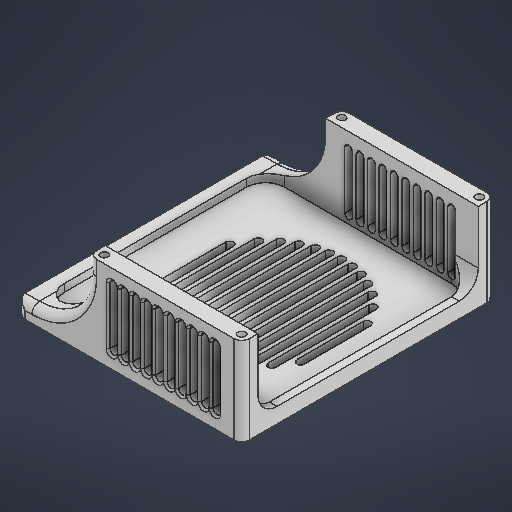
# Autodesk Inventor part: FLOOR PARTS
Saved by Autodesk Inventor 2027.1 (Build 311270010, 270A)
## iProperties
Created: 2026-10-10
Part Number: FLOOR PARTS
Material: 일반
Document SubType Name: Modeling
Designer: work
Density: 1 g/cm^3
Appearance: 기본값
Author: work
Autodesk Inventor part; units mm, degrees
ref_plane "YZ Plane" through (0, 0, 0) normal (1, 0, 0) x (0, 1, 0)
ref_plane "XZ Plane" through (0, 0, 0) normal (0, 1, 0) x (-1, 0, 0)
ref_plane "XY Plane" through (0, 0, 0) normal (0, 0, 1) x (1, 0, 0)
sketch "스케치1" plane through (0, 0, 0) normal (0, 1, 0) x (-1, 0, 0)
  line L0 (0, 0) -> (72, 0) construction
  line L1 (72, 0) -> (72, -124.5) construction
  line L2 (72, -124.5) -> (0, -124.5) construction
  line L3 (0, -124.5) -> (0, 0) construction
  line L4 (76, -128.5) -> (76, 4)
  line L5 (76, 4) -> (-4, 4)
  line L6 (-4, 4) -> (-4, -128.5)
  line L7 (-4, -128.5) -> (76, -128.5)
  circle A0 centre (72, 0) radius 2
  circle A1 centre (0, 0) radius 2
  circle A2 centre (0, -124.5) radius 2
  circle A3 centre (72, -124.5) radius 2
  line L8 (97.5, -4.5) -> (10, -4.5)
  line L9 (0, -14.5) -> (0, -110)
  line L10 (10, -120) -> (97.5, -120)
  line L11 (107.5, -110) -> (107.5, -14.5)
  arc A4 (10, -4.5) -> (0, -14.5) centre (10, -14.5) ccw
  arc A5 (0, -110) -> (10, -120) centre (10, -110) ccw
  line L12 (-4, -4.5) -> (10, -4.5)
  line L13 (-4, -120) -> (10, -120)
  arc A6 (107.5, -14.5) -> (97.5, -4.5) centre (97.5, -14.5) ccw
  arc A7 (97.5, -120) -> (107.5, -110) centre (97.5, -110) ccw
  line L14 (76, 4) -> (113.5, 4)
  line L15 (113.5, 4) -> (113.5, -128.5)
  line L16 (113.5, -128.5) -> (76, -128.5)
  line L17 (76, -128.5) -> (76, 4)
  point P0 (0, -120)
  point P1 (0, -4.5)
  point P2 (107.5, -120)
  point P3 (0, -62.25)
  point P4 (76, -4.5)
  point P5 (76, -120)
  dimension "d0" = 124.5
  dimension "d1" = 72
  dimension "d2" = 4
  dimension "d3" = 4
  dimension "d4" = 4
  dimension "d5" = 4
  dimension "d6" = 4
  dimension "d7" = 115.5
  dimension "d8" = 107.5
  dimension "d9" = 10
  dimension "d16" = 10
  dimension "d17" = 6
  constraints: 36 end point, 9 parallel, 8 centre point, 8 point on circle, 8 point on line, 8 tangent, 4 coincident, 4 horizontal, 4 perpendicular, 2 equal radius, 2 midpoint, 3 other
  measures "d0" distance of L2.end L0.start
  measures "d1" distance of L0.start L0.end
  measures "d2" distance between parallel lines of L1 L4
  measures "d3" diameter of A0
  measures "d4" diameter of A1
  measures "d5" diameter of A2
  measures "d6" diameter of A3
  measures "d7" distance of point (0, -4.5) point (0, -120)
  measures "d8" distance of point (0, -120) point (107.5, -120)
  measures "d9" radius of A4
  measures "d16" radius of A6
  measures "d17" distance between parallel lines of L15 L11
extrude "돌출1" add sketch "스케치1" along normal blind 4 contours L7 L6 L13 L10 L4 | L10 A5 L9 A4 L8 L4 | L4 L8 A6 L11 A7 L10 | L8 L12 L6 L5 L4 | L13 L6 L12 A4 L9 A5 | A0 | A1 | A2 | A3
extrude "돌출2" add sketch "스케치1" along normal blind 8 contours L7 L6 L13 L10 L4 | L4 L10 A7 L11 A6 L8 L14 L15 L16 | L8 L12 L6 L5 L4 | L13 L6 L12 A4 L9 A5
extrude "돌출3" add sketch "스케치1" along normal blind 46 contours L7 L6 L13 L10 L4 | L8 L12 L6 L5 L4
fillet "모깎기1" radius 30 2 edges at (-76, 8, -124.25) (-76, 8, -0.25)
sketch "스케치2" plane through (4, 0, -128.5) normal (0, 0, -1) x (-1, 0, 0)
  line L0 (8, 38) -> (8, 8) construction
  line L1 (6, 38) -> (6, 8)
  line L2 (10, 8) -> (10, 38)
  arc A0 (10, 38) -> (6, 38) centre (8, 38) ccw
  arc A1 (6, 8) -> (10, 8) centre (8, 8) ccw
  line L3 (0, 0) -> (117.5, 0) projected
  line L4 (0, 46) -> (80, 46) projected
  line L5 (0, 0) -> (0, 46) projected
  line L6 (14, 38) -> (14, 8) construction
  line L7 (12, 38) -> (12, 8)
  line L8 (16, 8) -> (16, 38)
  arc A2 (16, 38) -> (12, 38) centre (14, 38) ccw
  arc A3 (12, 8) -> (16, 8) centre (14, 8) ccw
  line L9 (20, 38) -> (20, 8) construction
  line L10 (18, 38) -> (18, 8)
  line L11 (22, 8) -> (22, 38)
  arc A4 (22, 38) -> (18, 38) centre (20, 38) ccw
  arc A5 (18, 8) -> (22, 8) centre (20, 8) ccw
  line L12 (26, 38) -> (26, 8) construction
  line L13 (24, 38) -> (24, 8)
  line L14 (28, 8) -> (28, 38)
  arc A6 (28, 38) -> (24, 38) centre (26, 38) ccw
  arc A7 (24, 8) -> (28, 8) centre (26, 8) ccw
  line L15 (32, 38) -> (32, 8) construction
  line L16 (30, 38) -> (30, 8)
  line L17 (34, 8) -> (34, 38)
  arc A8 (34, 38) -> (30, 38) centre (32, 38) ccw
  arc A9 (30, 8) -> (34, 8) centre (32, 8) ccw
  line L18 (38, 38) -> (38, 8) construction
  line L19 (36, 38) -> (36, 8)
  line L20 (40, 8) -> (40, 38)
  arc A10 (40, 38) -> (36, 38) centre (38, 38) ccw
  arc A11 (36, 8) -> (40, 8) centre (38, 8) ccw
  line L21 (44, 38) -> (44, 8) construction
  line L22 (42, 38) -> (42, 8)
  line L23 (46, 8) -> (46, 38)
  arc A12 (46, 38) -> (42, 38) centre (44, 38) ccw
  arc A13 (42, 8) -> (46, 8) centre (44, 8) ccw
  line L24 (50, 38) -> (50, 8) construction
  line L25 (48, 38) -> (48, 8)
  line L26 (52, 8) -> (52, 38)
  arc A14 (52, 38) -> (48, 38) centre (50, 38) ccw
  arc A15 (48, 8) -> (52, 8) centre (50, 8) ccw
  line L27 (56, 38) -> (56, 8) construction
  line L28 (54, 38) -> (54, 8)
  line L29 (58, 8) -> (58, 38)
  arc A16 (58, 38) -> (54, 38) centre (56, 38) ccw
  arc A17 (54, 8) -> (58, 8) centre (56, 8) ccw
  line L30 (62, 38) -> (62, 8) construction
  line L31 (60, 38) -> (60, 8)
  line L32 (64, 8) -> (64, 38)
  arc A18 (64, 38) -> (60, 38) centre (62, 38) ccw
  arc A19 (60, 8) -> (64, 8) centre (62, 8) ccw
  line L33 (68, 38) -> (68, 8) construction
  line L34 (66, 38) -> (66, 8)
  line L35 (70, 8) -> (70, 38)
  arc A20 (70, 38) -> (66, 38) centre (68, 38) ccw
  arc A21 (66, 8) -> (70, 8) centre (68, 8) ccw
  line L36 (74, 38) -> (74, 8) construction
  line L37 (72, 38) -> (72, 8)
  line L38 (76, 8) -> (76, 38)
  arc A22 (76, 38) -> (72, 38) centre (74, 38) ccw
  arc A23 (72, 8) -> (76, 8) centre (74, 8) ccw
  point P0 (4, 0)
  point P1 (8, 23)
  point P2 (14, 23)
  point P3 (20, 23)
  point P4 (26, 23)
  point P5 (32, 23)
  point P6 (38, 23)
  point P7 (44, 23)
  point P8 (50, 23)
  point P9 (56, 23)
  point P10 (62, 23)
  point P11 (68, 23)
  point P12 (74, 23)
  dimension "d19" = 8
  dimension "d20" = 4
  dimension "d21" = 8
  dimension "d22" = 8
  dimension "d25" = 6
  constraints: 96 end point, 48 point on circle, 24 centre point, 4 tangent, 1 horizontal, 1 midpoint, 1 parallel, 1 vertical, 132 other
  measures "d19" distance from line of L3 L0.end
  measures "d20" distance between parallel lines of L2 L1
  measures "d21" distance from line of L4 L0.start
  measures "d22" distance between parallel lines of L5 L0
  measures "d25" distance of L1.start L7.start
extrude "돌출4" cut sketch "스케치2" against normal through all contours A2 L8 A3 L7 | A4 L11 A5 L10 | A6 L14 A7 L13 | A8 L17 A9 L16 | A10 L20 A11 L19 | A12 L23 A13 L22 | A14 L26 A15 L25 | A16 L29 A17 L28 | A18 L32 A19 L31 | A20 L35 A21 L34
fillet "모깎기2" radius 10 2 edges at (-2, 8, -4.5) (-2, 8, -120)
fillet "모깎기3" radius 4 10 edges at (4, 23, -128.5) (4, 23, 4) (-113.5, 4, -128.5) (-113.5, 4, 4) (-84.7868, 16.7868, 4) (-109.75, 8, 4) (-76, 42, 4) (-109.75, 8, -128.5) (-76, 42, -128.5) (-84.7868, 16.7868, -128.5)
sketch "스케치3" plane through (0, 4, 0) normal (0, 1, 0) x (1, 0, 0)
  circle A0 centre (-50, 62.25) radius 40 construction
  line L0 (0, 110) -> (0, 14.5) projected
  line L1 (-90, 62.25) -> (-10, 62.25) construction
  line L2 (-50, 102.25) -> (-50, 22.25) construction
  line L3 (-52, 102.25) -> (-52, 22.25)
  line L4 (-48, 22.25) -> (-48, 102.25)
  arc A1 (-48, 102.25) -> (-52, 102.25) centre (-50, 102.25) ccw
  arc A2 (-52, 22.25) -> (-48, 22.25) centre (-50, 22.25) ccw
  line L5 (-56, 101.7974) -> (-56, 22.7026) construction
  line L6 (-58, 101.7974) -> (-58, 22.7026)
  line L7 (-54, 22.7026) -> (-54, 101.7974)
  arc A3 (-54, 101.7974) -> (-58, 101.7974) centre (-56, 101.7974) ccw
  arc A4 (-58, 22.7026) -> (-54, 22.7026) centre (-56, 22.7026) ccw
  line L8 (-62, 100.4076) -> (-62, 24.0924) construction
  line L9 (-64, 100.4076) -> (-64, 24.0924)
  line L10 (-60, 24.0924) -> (-60, 100.4076)
  arc A5 (-60, 100.4076) -> (-64, 100.4076) centre (-62, 100.4076) ccw
  arc A6 (-64, 24.0924) -> (-60, 24.0924) centre (-62, 24.0924) ccw
  line L11 (-68, 97.9711) -> (-68, 26.5289) construction
  line L12 (-70, 97.9711) -> (-70, 26.5289)
  line L13 (-66, 26.5289) -> (-66, 97.9711)
  arc A7 (-66, 97.9711) -> (-70, 97.9711) centre (-68, 97.9711) ccw
  arc A8 (-70, 26.5289) -> (-66, 26.5289) centre (-68, 26.5289) ccw
  line L14 (-74, 94.25) -> (-74, 30.25) construction
  line L15 (-76, 94.25) -> (-76, 30.25)
  line L16 (-72, 30.25) -> (-72, 94.25)
  arc A9 (-72, 94.25) -> (-76, 94.25) centre (-74, 94.25) ccw
  arc A10 (-76, 30.25) -> (-72, 30.25) centre (-74, 30.25) ccw
  line L17 (-80, 88.7075) -> (-80, 35.7925) construction
  line L18 (-82, 88.7075) -> (-82, 35.7925)
  line L19 (-78, 35.7925) -> (-78, 88.7075)
  arc A11 (-78, 88.7075) -> (-82, 88.7075) centre (-80, 88.7075) ccw
  arc A12 (-82, 35.7925) -> (-78, 35.7925) centre (-80, 35.7925) ccw
  line L20 (-86, 79.6856) -> (-86, 44.8144) construction
  line L21 (-88, 79.6856) -> (-88, 44.8144)
  line L22 (-84, 44.8144) -> (-84, 79.6856)
  arc A13 (-84, 79.6856) -> (-88, 79.6856) centre (-86, 79.6856) ccw
  arc A14 (-88, 44.8144) -> (-84, 44.8144) centre (-86, 44.8144) ccw
  circle A15 centre (-50, 62.25) radius 40 construction
  line L23 (-10, 62.25) -> (-90, 62.25) construction
  line L24 (-44, 101.7974) -> (-44, 22.7026) construction
  line L25 (-42, 101.7974) -> (-42, 22.7026)
  line L26 (-46, 22.7026) -> (-46, 101.7974)
  arc A16 (-42, 101.7974) -> (-46, 101.7974) centre (-44, 101.7974) ccw
  arc A17 (-46, 22.7026) -> (-42, 22.7026) centre (-44, 22.7026) ccw
  line L27 (-38, 100.4076) -> (-38, 24.0924) construction
  line L28 (-36, 100.4076) -> (-36, 24.0924)
  line L29 (-40, 24.0924) -> (-40, 100.4076)
  arc A18 (-36, 100.4076) -> (-40, 100.4076) centre (-38, 100.4076) ccw
  arc A19 (-40, 24.0924) -> (-36, 24.0924) centre (-38, 24.0924) ccw
  line L30 (-32, 97.9711) -> (-32, 26.5289) construction
  line L31 (-30, 97.9711) -> (-30, 26.5289)
  line L32 (-34, 26.5289) -> (-34, 97.9711)
  arc A20 (-30, 97.9711) -> (-34, 97.9711) centre (-32, 97.9711) ccw
  arc A21 (-34, 26.5289) -> (-30, 26.5289) centre (-32, 26.5289) ccw
  line L33 (-26, 94.25) -> (-26, 30.25) construction
  line L34 (-24, 94.25) -> (-24, 30.25)
  line L35 (-28, 30.25) -> (-28, 94.25)
  arc A22 (-24, 94.25) -> (-28, 94.25) centre (-26, 94.25) ccw
  arc A23 (-28, 30.25) -> (-24, 30.25) centre (-26, 30.25) ccw
  line L36 (-20, 88.7075) -> (-20, 35.7925) construction
  line L37 (-18, 88.7075) -> (-18, 35.7925)
  line L38 (-22, 35.7925) -> (-22, 88.7075)
  arc A24 (-18, 88.7075) -> (-22, 88.7075) centre (-20, 88.7075) ccw
  arc A25 (-22, 35.7925) -> (-18, 35.7925) centre (-20, 35.7925) ccw
  line L39 (-14, 79.6856) -> (-14, 44.8144) construction
  line L40 (-12, 79.6856) -> (-12, 44.8144)
  line L41 (-16, 44.8144) -> (-16, 79.6856)
  arc A26 (-12, 79.6856) -> (-16, 79.6856) centre (-14, 79.6856) ccw
  arc A27 (-16, 44.8144) -> (-12, 44.8144) centre (-14, 44.8144) ccw
  point P0 (0, 0)
  point P1 (0, 62.25)
  point P2 (0, 62.25)
  point P3 (-56, 62.25)
  point P4 (-62, 62.25)
  point P5 (-68, 62.25)
  point P6 (-74, 62.25)
  point P7 (-80, 62.25)
  point P8 (-86, 62.25)
  point P9 (-44, 62.25)
  point P10 (-38, 62.25)
  point P11 (-32, 62.25)
  point P12 (-26, 62.25)
  point P13 (-20, 62.25)
  point P14 (-14, 62.25)
  dimension "d34" = 80
  dimension "d35" = 50
  dimension "d36" = 80
  dimension "d37" = 4
  dimension "d38" = 4
  dimension "d39" = 4
  dimension "d40" = 4
  dimension "d41" = 4
  dimension "d42" = 6
  dimension "d43" = 6
  dimension "d44" = 6
  dimension "d45" = 6
  dimension "d46" = 4
  dimension "d47" = 4
  dimension "d48" = 6
  dimension "d49" = 6
  constraints: 108 end point, 52 point on circle, 44 symmetric about line, 28 tangent, 26 centre point, 13 parallel, 12 point on line, 9 midpoint, 2 vertical, 1 horizontal, 1 horizontal alignment, 33 other
  measures "d35" distance of point (0, 62.25) point (-50, 62.25)
  measures "d36" distance of L1.start L1.end
  measures "d37" diameter of A2
  measures "d38" diameter of A4
  measures "d39" diameter of A6
  measures "d40" diameter of A8
  measures "d41" diameter of A10
  measures "d42" distance between parallel lines of L2 L5
  measures "d43" distance between parallel lines of L8 L5
  measures "d44" distance between parallel lines of L8 L11
  measures "d45" distance between parallel lines of L14 L11
  measures "d46" diameter of A12
  measures "d47" diameter of A14
  measures "d48" distance between parallel lines of L17 L14
  measures "d49" distance between parallel lines of L20 L17
extrude "돌출5" cut sketch "스케치3" against normal through all
sketch "스케치4" plane through (0, 0, 0) normal (0, -1, 0) x (1, 0, 0)
  arc A0 (-46, -101.7974) -> (-42, -101.7974) centre (-44, -101.7974) ccw construction
  line L0 (-46, -101.7974) -> (-46, -22.7026) construction
  arc A1 (-42, -22.7026) -> (-46, -22.7026) centre (-44, -22.7026) ccw construction
  line L1 (-42, -22.7026) -> (-42, -101.7974) construction
  line L2 (-72, -30.25) -> (-72, -94.25) construction
  arc A2 (-76, -94.25) -> (-72, -94.25) centre (-74, -94.25) ccw construction
  line L3 (-76, -94.25) -> (-76, -30.25) construction
  arc A3 (-72, -30.25) -> (-76, -30.25) centre (-74, -30.25) ccw construction
  line L4 (-60, -24.0924) -> (-60, -100.4076) construction
  arc A4 (-64, -100.4076) -> (-60, -100.4076) centre (-62, -100.4076) ccw construction
  line L5 (-64, -100.4076) -> (-64, -24.0924) construction
  arc A5 (-60, -24.0924) -> (-64, -24.0924) centre (-62, -24.0924) ccw construction
  arc A6 (-40, -100.4076) -> (-36, -100.4076) centre (-38, -100.4076) ccw construction
  line L6 (-40, -100.4076) -> (-40, -24.0924) construction
  arc A7 (-36, -24.0924) -> (-40, -24.0924) centre (-38, -24.0924) ccw construction
  line L7 (-36, -24.0924) -> (-36, -100.4076) construction
  arc A8 (-28, -94.25) -> (-24, -94.25) centre (-26, -94.25) ccw construction
  line L8 (-28, -94.25) -> (-28, -30.25) construction
  arc A9 (-24, -30.25) -> (-28, -30.25) centre (-26, -30.25) ccw construction
  line L9 (-24, -30.25) -> (-24, -94.25) construction
  arc A10 (-22, -88.7075) -> (-18, -88.7075) centre (-20, -88.7075) ccw construction
  line L10 (-22, -88.7075) -> (-22, -35.7925) construction
  arc A11 (-18, -35.7925) -> (-22, -35.7925) centre (-20, -35.7925) ccw construction
  line L11 (-18, -35.7925) -> (-18, -88.7075) construction
  arc A12 (-16, -79.6856) -> (-12, -79.6856) centre (-14, -79.6856) ccw construction
  line L12 (-16, -79.6856) -> (-16, -44.8144) construction
  arc A13 (-12, -44.8144) -> (-16, -44.8144) centre (-14, -44.8144) ccw construction
  line L13 (-12, -44.8144) -> (-12, -79.6856) construction
  line L14 (-78, -35.7925) -> (-78, -88.7075) construction
  arc A14 (-82, -88.7075) -> (-78, -88.7075) centre (-80, -88.7075) ccw construction
  line L15 (-82, -88.7075) -> (-82, -35.7925) construction
  arc A15 (-78, -35.7925) -> (-82, -35.7925) centre (-80, -35.7925) ccw construction
  arc A16 (-34, -97.9711) -> (-30, -97.9711) centre (-32, -97.9711) ccw construction
  line L16 (-34, -97.9711) -> (-34, -26.5289) construction
  arc A17 (-30, -26.5289) -> (-34, -26.5289) centre (-32, -26.5289) ccw construction
  line L17 (-30, -26.5289) -> (-30, -97.9711) construction
  line L18 (-54, -22.7026) -> (-54, -101.7974) construction
  arc A18 (-58, -101.7974) -> (-54, -101.7974) centre (-56, -101.7974) ccw construction
  line L19 (-58, -101.7974) -> (-58, -22.7026) construction
  arc A19 (-54, -22.7026) -> (-58, -22.7026) centre (-56, -22.7026) ccw construction
  line L20 (-66, -26.5289) -> (-66, -97.9711) construction
  arc A20 (-70, -97.9711) -> (-66, -97.9711) centre (-68, -97.9711) ccw construction
  line L21 (-70, -97.9711) -> (-70, -26.5289) construction
  arc A21 (-66, -26.5289) -> (-70, -26.5289) centre (-68, -26.5289) ccw construction
  line L22 (-84, -44.8144) -> (-84, -79.6856) construction
  arc A22 (-88, -79.6856) -> (-84, -79.6856) centre (-86, -79.6856) ccw construction
  line L23 (-88, -79.6856) -> (-88, -44.8144) construction
  arc A23 (-84, -44.8144) -> (-88, -44.8144) centre (-86, -44.8144) ccw construction
  line L24 (-48, -22.25) -> (-48, -102.25) construction
  arc A24 (-52, -102.25) -> (-48, -102.25) centre (-50, -102.25) ccw construction
  line L25 (-52, -102.25) -> (-52, -22.25) construction
  arc A25 (-48, -22.25) -> (-52, -22.25) centre (-50, -22.25) ccw construction
  arc A26 (-109.5, 4) -> (-113.5, 0) centre (-109.5, 0) ccw construction
  line L26 (-113.5, -124.5) -> (-113.5, 0) construction
  arc A27 (-113.5, -124.5) -> (-109.5, -128.5) centre (-109.5, -124.5) ccw construction
  line L27 (0, -128.5) -> (-109.5, -128.5) construction
  arc A28 (0, -128.5) -> (4, -124.5) centre (0, -124.5) ccw construction
  line L28 (4, 0) -> (4, -124.5) construction
  arc A29 (4, 0) -> (0, 4) centre (0, 0) ccw construction
  line L29 (-109.5, 4) -> (0, 4) construction
  line L30 (-103.5, -6) -> (-6, -6) construction
  line L31 (-6, -6) -> (-6, -118.5) construction
  line L32 (-6, -118.5) -> (-103.5, -118.5) construction
  line L33 (-103.5, -118.5) -> (-103.5, -6) construction
  circle A30 centre (-6, -118.5) radius 6
  circle A31 centre (-6, -6) radius 6
  circle A32 centre (-103.5, -6) radius 6
  circle A33 centre (-103.5, -118.5) radius 6
  point P0 (0, 0)
  dimension "d52" = 10
  dimension "d53" = 12
  dimension "d54" = 12
  dimension "d55" = 12
  dimension "d56" = 12
  constraints: 8 end point, 4 centre point, 4 coincident, 3 other
  measures "d52" distance between parallel lines of L26 L33
  measures "d53" diameter of A30
  measures "d54" diameter of A31
  measures "d55" diameter of A32
  measures "d56" diameter of A33
extrude "돌출6" cut sketch "스케치4" against normal blind 0.5
chamfer "모따기1" distance 1 angle 45 84 edges at (-46, 40, 4) (-44, 23, 4) (-46, 6, 4) (-48, 23, 4) (-36, 23, 4) (-34, 40, 4) (-32, 23, 4) (-34, 6, 4) (-20, 23, 4) (-22, 6, 4) (-24, 23, 4) (-22, 40, 4) (-12, 23, 4) (-10, 40, 4) (-8, 23, 4) (-10, 6, 4) (-60, 23, 4) (-58, 40, 4) (-56, 23, 4) (-58, 6, 4) (-52, 40, 4) (-50, 23, 4) (-52, 6, 4) (-54, 23, 4) (-38, 23, 4) (-40, 6, 4) (-42, 23, 4) (-40, 40, 4) (-28, 40, 4) (-26, 23, 4) (-28, 6, 4) (-30, 23, 4) (-14, 23, 4) (-16, 6, 4) (-18, 23, 4) (-16, 40, 4) (-62, 23, 4) (-64, 6, 4) (-66, 23, 4) (-64, 40, 4) (-70, 4, 0) (2, 4, 0) (-48, 23, -128.5) (-46, 6, -128.5) (-44, 23, -128.5) (-46, 40, -128.5) (-20, 23, -128.5) (-22, 40, -128.5) (-24, 23, -128.5) (-22, 6, -128.5) (-40, 40, -128.5) (-42, 23, -128.5) (-40, 6, -128.5) (-38, 23, -128.5) (-62, 23, -128.5) (-64, 40, -128.5) (-66, 23, -128.5) (-64, 6, -128.5) (-58, 6, -128.5) (-56, 23, -128.5) (-58, 40, -128.5) (-60, 23, -128.5) (-30, 23, -128.5) (-28, 6, -128.5) (-26, 23, -128.5) (-28, 40, -128.5) (-50, 23, -128.5) (-52, 40, -128.5) (-54, 23, -128.5) (-52, 6, -128.5) (-14, 23, -128.5) (-16, 40, -128.5) (-18, 23, -128.5) (-16, 6, -128.5) (-70, 4, -124.5) (-32, 23, -128.5) (-34, 40, -128.5) (-36, 23, -128.5) (-34, 6, -128.5) (2, 4, -124.5) (-10, 40, -128.5) (-12, 23, -128.5) (-10, 6, -128.5) (-8, 23, -128.5)
